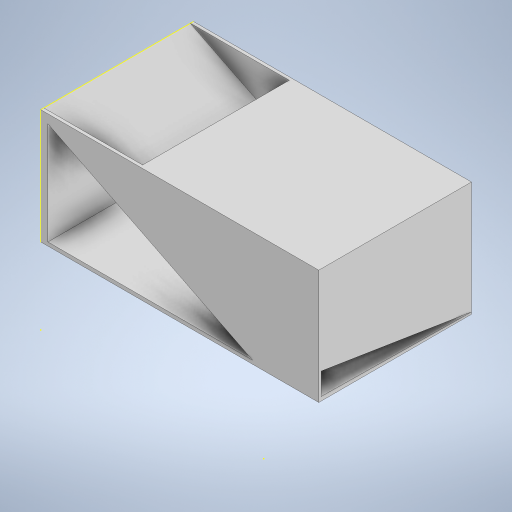
# Autodesk Inventor part: entenoir22
Saved by Autodesk Inventor 2024.3 (Build 283343000, 343)
## iProperties
Created: 2025-03-03
Part Number: entenoir22
Material: Générique
Document SubType Name: Modeling
Designer: abouabdellah
Density: 1 g/cm^3
Appearance: Par défaut
Author: abouabdellah
Autodesk Inventor part; units mm, degrees
ref_plane "YZ Plane" through (0, 0, 0) normal (1, 0, 0) x (0, 1, 0)
ref_plane "XZ Plane" through (0, 0, 0) normal (0, 1, 0) x (-1, 0, 0)
ref_plane "XY Plane" through (0, 0, 0) normal (0, 0, 1) x (1, 0, 0)
sketch "Esquisse1" plane through (0, 0, 0) normal (0, 0, 1) x (1, 0, 0)
  line L0 (15.0827, 100) -> (315.0827, 100)
  line L1 (315.0827, 100) -> (315.0827, 250)
  line L2 (315.0827, 250) -> (15.0827, 250)
  line L3 (15.0827, 250) -> (15.0827, 100)
  line L4 (15.0827, 250) -> (315.0827, 100)
  point P0 (0, 0)
  dimension "d0" = 150
  dimension "d1" = 300
  constraints: 10 end point, 2 parallel, 1 horizontal, 1 perpendicular
  measures "d0" distance of L0.end L1.end
  measures "d1" distance of L1.end L2.end
extrude "Extrusion1" add sketch "Esquisse1" against normal blind 200 contours L3 L4 L0
sketch "Esquisse2" plane through (15.0827, 100, 0) normal (0, -1, 0) x (1, 0, 0)
  line L0 (300, 0) -> (300, -200) projected
  line L1 (300, -200) -> (360.3401, -200)
  line L2 (360.3401, -200) -> (360.3401, 0)
  line L3 (360.3401, 0) -> (300, 0)
  line L4 (300, 0) -> (300, -200)
  point P0 (-15.0827, 0)
  constraints: 8 end point, 3 perpendicular, 1 horizontal
extrude "Extrusion2" add sketch "Esquisse2" against normal blind 4
sketch "Esquisse3" plane through (375.4228, 100, 0) normal (1, 0, 0) x (0, 0, -1)
  line L0 (0, 150) -> (0, 0) projected
  line L1 (0, 0) -> (0, 150)
  line L2 (0, 150) -> (200, 150)
  line L3 (200, 0) -> (200, 150) projected
  line L4 (200, 150) -> (200, 0)
  line L5 (200, 0) -> (0, 0)
  point P0 (0, -100)
  constraints: 8 end point, 2 collinear, 2 perpendicular
extrude "Extrusion3" add sketch "Esquisse3" along normal blind 4
sketch "Esquisse4" plane through (375.4228, 250, 0) normal (0, 1, 0) x (1, 0, 0)
  line L0 (0, 200) -> (0, 0) projected
  line L1 (0, 0) -> (-230.6363, 0)
  line L2 (-360.3401, 0) -> (-60.3401, 0) projected
  line L3 (-60.3401, 200) -> (-360.3401, 200) projected
  line L4 (0, 200) -> (-60.3401, 200) projected
  line L5 (-230.6363, 200) -> (0, 200)
  line L6 (0, 200) -> (0, 0)
  line L7 (-230.6363, 0) -> (-230.6363, 200)
  point P0 (-375.4228, 0)
  constraints: 8 end point, 2 point on line, 1 horizontal, 1 perpendicular, 1 vertical
extrude "Extrusion4" add sketch "Esquisse4" against normal blind 4
sketch "Esquisse6" plane through (0, 0, 0) normal (0, 0, 1) x (1, 0, 0)
  line L0 (315.0827, 104) -> (307.0827, 104)
  line L1 (15.0827, 250) -> (315.0827, 100) projected
  line L2 (315.0827, 100) -> (315.0827, 104) projected
  line L3 (315.0827, 100) -> (315.0827, 104)
  point P0 (0, 0)
  constraints: 4 end point, 1 collinear, 1 point on line
extrude "Extrusion6" add sketch "Esquisse6" against normal blind 200
sketch "Esquisse7" plane through (0, 0, 0) normal (0, 0, 1) x (1, 0, 0)
  line L0 (375.4228, 246) -> (144.7865, 246) projected
  line L1 (307.0827, 104) -> (15.0827, 250) projected
  line L2 (375.4228, 104) -> (307.0827, 104) projected
  line L3 (307.0827, 104) -> (375.4228, 104)
  line L4 (375.4228, 246) -> (375.4228, 104) projected
  line L5 (375.4228, 104) -> (375.4228, 246)
  line L6 (375.4228, 246) -> (144.7865, 246)
  line L7 (144.7865, 250) -> (144.7865, 246) projected
  line L8 (144.7865, 250) -> (15.0827, 250)
  line L9 (307.0827, 104) -> (375.4228, 104)
  line L10 (375.4228, 246) -> (144.7865, 246)
  line L11 (144.7865, 250) -> (379.4228, 250) projected
  line L12 (144.7865, 246) -> (144.7865, 250)
  point P0 (0, 0)
  point P1 (144.7865, 185.1481)
  constraints: 14 end point, 4 collinear, 2 perpendicular, 1 point on line, 1 vertical
extrude "Extrusion7" add sketch "Esquisse7" against normal blind 4
sketch "Esquisse11" plane through (0, 0, -200) normal (0, 0, -1) x (-1, 0, 0)
  line L0 (-144.7865, 250) -> (-144.7865, 246) projected
  line L1 (-144.7865, 246) -> (-144.7865, 250)
  line L2 (-15.0827, 250) -> (-307.0827, 104) projected
  line L3 (-144.7865, 250) -> (-15.0827, 250)
  line L4 (-15.0827, 250) -> (-307.0827, 104)
  line L5 (-307.0827, 104) -> (-307.0827, 140.1413)
  line L6 (-307.0827, 140.1413) -> (-375.4228, 140.1413)
  line L7 (-375.4228, 104) -> (-375.4228, 246) projected
  line L8 (-144.7865, 246) -> (-375.4228, 246) projected
  line L9 (-375.4228, 246) -> (-144.7865, 246)
  line L10 (-144.7865, 250) -> (-379.4228, 250) projected
  point P0 (0, 0)
  constraints: 12 end point, 2 parallel, 1 collinear, 1 horizontal, 1 perpendicular, 1 point on line, 1 vertical
extrude "Extrusion9" add sketch "Esquisse11" against normal blind 4
sketch "Esquisse15" plane through (375.4228, 100, 0) normal (-1, 0, 0) x (0, 0, 1)
  line L0 (-4, 4) -> (-200, 4) projected
  line L1 (-72.2155, 4) -> (-200, 4)
  line L2 (-200, 4) -> (-70.8518, 26.8133)
  line L3 (-72.2155, 4) -> (-4, 4)
  line L4 (-4, 4) -> (-4, 146) projected
  line L5 (-4, 38.6223) -> (-70.8518, 26.8133)
  point P0 (0, -100)
  point P1 (-70.8518, 4)
  constraints: 8 end point, 2 collinear, 2 point on line
extrude "Extrusion11" add sketch "Esquisse15" along normal blind 139.5
sketch "Esquisse19" plane through (307.1728, 100, 0) normal (-1, 0, 0) x (0, 0, 1)
  line L0 (-4, 4) -> (-196, 4) projected
  line L1 (-196, 4) -> (-4, 4)
  line L2 (-4, 4) -> (-4, 39.1619)
  line L3 (-4, 38.6223) -> (-194.9752, 4.8876)
  line L4 (-4, 38.6223) -> (-200, 4) projected
  point P0 (0, -100)
  constraints: 6 end point, 1 horizontal, 1 perpendicular, 1 point on line
sketch "Esquisse20" plane through (0, 0, -200) normal (0, 0, -1) x (-1, 0, 0)
  line L0 (-292.6348, 104.7066) -> (-24.7804, 238.6338)
  line L1 (-305.6696, 104.7066) -> (-15.0827, 250) projected
  line L2 (-24.7804, 238.6338) -> (-24.7804, 104.7066)
  line L3 (-24.7804, 104.7066) -> (-292.6348, 104.7066)
  point P0 (0, 0)
  constraints: 6 end point, 1 parallel, 1 perpendicular, 1 vertical
extrude "Extrusion15" cut sketch "Esquisse20" against normal blind 208
sketch "Esquisse21" plane through (379.4228, 100, 0) normal (1, 0, 0) x (0, 0, -1)
  line L0 (3.1922, 33.981) -> (200, 2.6885)
  line L1 (200, 2.6885) -> (43.0551, 4.7066)
  line L2 (3.1922, 33.981) -> (3.1922, 33.981)
  line L3 (4, 38.6223) -> (196, 4.7066) projected
  line L4 (3.1922, 33.981) -> (3.1922, 5.2192)
  line L5 (3.1922, 5.2192) -> (43.0551, 4.7066)
  point P0 (0, -100)
  point P1 (200, 4.7066)
  constraints: 10 end point, 1 collinear, 1 parallel, 1 vertical
extrude "Extrusion16" cut sketch "Esquisse21" against normal blind 72.25
sketch "Esquisse22" plane through (15.0827, 100, -200) normal (-1, 0, 0) x (0, 0, 1)
  line L0 (200, 150) -> (200, 0) projected
  line L1 (200, 150) -> (196, 150) projected
  line L2 (196, 150) -> (4, 150) projected
  line L3 (4, 150) -> (0, 150) projected
  line L4 (0, 0) -> (0, 150) projected
  line L5 (200, 0) -> (0, 0) projected
  point P0 (200, -100)
